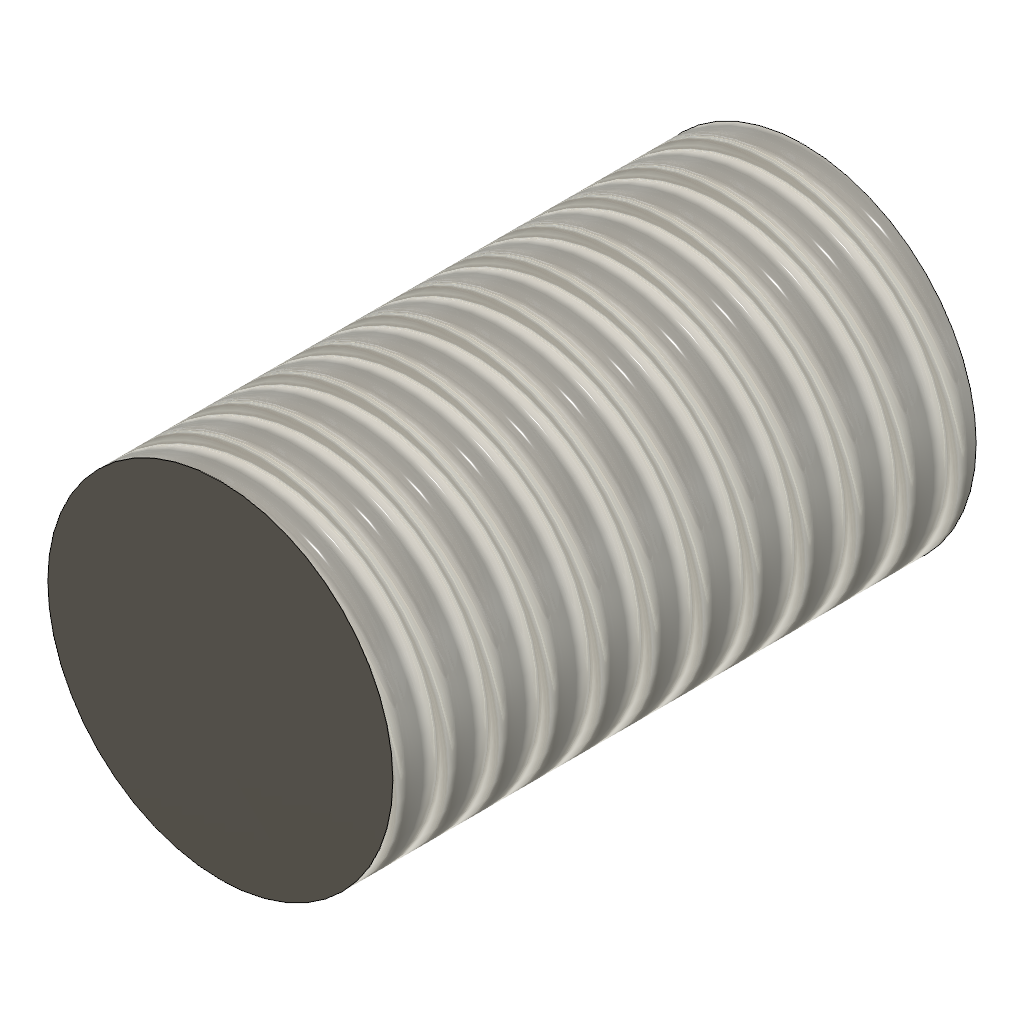
cosmetic_full (Autodesk Fusion 360 design; units mm, degrees)
part number: 2026-10-20-20-26-40-398
Autodesk Fusion 360 part; units mm, degrees
sketch "Sketch1" plane through (0, 0, 0) normal (0, 0, 1) x (1, 0, 0)
  circle A0 centre (0, 0) radius 6
extrude "Extrude1" add sketch "Sketch1" along normal blind 20
thread "ProbeThread" "ISO Metric profile 12.0 M12x1.75 M12x1.75 6g" major diameter 11.8335 minor diameter 9.8365 pitch 1.75 angle 60 resizes the face on face at (5.9925, -0.2991, 13.3333)
